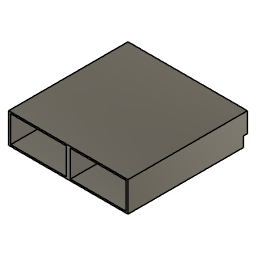
360degrees (Autodesk Fusion 360 design; units mm, degrees)
Autodesk Fusion 360 part; units mm, degrees
sketch "Sketch1" plane through (0, 0, 0) normal (0, 0, 1) x (1, 0, 0)
  line L0 (0, 0) -> (60, 0)
  line L1 (60, 0) -> (60, 60)
  line L2 (60, 60) -> (0, 60)
  line L3 (0, 60) -> (0, 0)
  dimension "d1" = 60
  dimension "d2" = 60
  constraint horizontal L0
  constraint vertical L1
  constraint horizontal L2
  constraint vertical L3
  constraint coincident L0.start L3.end
  measures "d1" distance of L0.start L0.end
  measures "d2" distance of L0.start L2.end
extrude "Extrude1" add sketch "Sketch1" along normal blind 15 makes body 1
sketch "Sketch2" plane through (0, 0, 0) normal (0, -1, 0) x (1, 0, 0)
  line L0 (0, 0) -> (60, 0)
  line L1 (60, 0) -> (60, 15)
  line L2 (60, 15) -> (0, 15)
  line L3 (0, 15) -> (0, 0)
  line L4 (30, 0) -> (30, 15)
  line L5 (1, 14.25) -> (29, 14.25)
  line L6 (29, 14.25) -> (29, 0.75)
  line L7 (29, 0.75) -> (1, 0.75)
  line L8 (1, 0.75) -> (1, 14.25)
  line L9 (1, 14.25) -> (0, 14.25)
  line L10 (29, 14.25) -> (30, 14.25)
  line L11 (1, 14.25) -> (1, 15)
  line L12 (1, 0.75) -> (1, 0)
  line L13 (31, 14.25) -> (59, 14.25)
  line L14 (59, 14.25) -> (59, 0.75)
  line L15 (59, 0.75) -> (31, 0.75)
  line L16 (31, 0.75) -> (31, 14.25)
  line L17 (31, 14.25) -> (30, 14.25)
  line L18 (31, 14.25) -> (31, 15)
  line L19 (31, 0.75) -> (31, 0)
  line L20 (59, 14.25) -> (60, 14.25)
  dimension "d5" = 28
  dimension "d6" = 13.5
  dimension "d9" = 28
  dimension "d10" = 13.5
  constraint midpoint L0 L4.start
  constraint midpoint L2 L4.end
  constraint horizontal L5
  constraint vertical L6
  constraint horizontal L7
  constraint vertical L8
  constraint coincident L3 L9.end
  constraint perpendicular L3 L9
  constraint coincident L4 L10.end
  constraint perpendicular L4 L10
  constraint equal L9 L10
  constraint coincident L2 L11.end
  constraint perpendicular L2 L11
  constraint coincident L0 L12.end
  constraint perpendicular L0 L12
  constraint equal L11 L12
  constraint horizontal L13
  constraint vertical L14
  constraint horizontal L15
  constraint vertical L16
  constraint perpendicular L4 L17
  constraint coincident L2 L18.end
  constraint perpendicular L2 L18
  constraint coincident L0 L19.end
  constraint perpendicular L0 L19
  constraint coincident L1 L20.end
  constraint perpendicular L1 L20
  constraint equal L17 L20
  constraint equal L18 L19
  measures "d5" distance of L5.start L5.end
  measures "d6" distance of L5.start L7.end
  measures "d9" distance of L13.start L13.end
  measures "d10" distance of L13.start L15.end
extrude "Extrude2" cut sketch "Sketch2" against normal blind 30 contours L5 L6 L7 L8 | L13 L14 L15 L16 bodies 1
sketch "Sketch4" plane through (0, 30, 0) normal (0, -1, 0) x (1, 0, 0)
  line L0 (31, 0.75) -> (59, 0.75)
  line L1 (59, 0.75) -> (59, 14.25)
  line L2 (59, 14.25) -> (31, 14.25)
  line L3 (31, 14.25) -> (31, 0.75)
  line L4 (31, 0.75) -> (59, 0.75)
  line L5 (59, 0.75) -> (59, 10.75)
  line L6 (59, 10.75) -> (31, 10.75)
  line L7 (31, 10.75) -> (31, 0.75)
  dimension "d13" = 10
  constraint horizontal L4
  constraint vertical L5
  constraint horizontal L6
  constraint vertical L7
  constraint coincident L0.start L3.end
  measures "d13" distance of L0.start L6.end
sketch "Sketch5" plane through (0, 30, 0) normal (0, -1, 0) x (1, 0, 0)
  line L0 (1, 0.75) -> (29, 0.75)
  line L1 (29, 0.75) -> (29, 14.25)
  line L2 (29, 14.25) -> (1, 14.25)
  line L3 (1, 14.25) -> (1, 0.75)
  line L4 (1, 0.75) -> (29, 0.75)
  line L5 (29, 0.75) -> (29, 10.75)
  line L6 (29, 10.75) -> (1, 10.75)
  line L7 (1, 10.75) -> (1, 0.75)
  dimension "d14" = 10
  constraint horizontal L4
  constraint vertical L5
  constraint horizontal L6
  constraint vertical L7
  constraint coincident L0.start L3.end
  measures "d14" distance of L0.start L6.end
sketch "Sketch6" plane through (0, 0, 0) normal (0, 0, -1) x (1, 0, 0)
  line L0 (0, 0) -> (0, -60)
  line L1 (0, -60) -> (60, -60)
  line L2 (60, -60) -> (60, 0)
  line L3 (60, 0) -> (0, 0)
  line L4 (0, -30) -> (60, -30)
  line L5 (1, -59) -> (59, -59)
  line L6 (59, -59) -> (59, -31)
  line L7 (59, -31) -> (1, -31)
  line L8 (1, -31) -> (1, -59)
  line L9 (1, -59) -> (0, -59)
  line L10 (59, -59) -> (60, -59)
  line L11 (59, -59) -> (59, -60)
  line L12 (59, -31) -> (59, -30)
  dimension "d15" = 58
  dimension "d16" = 28
  constraint midpoint L0 L4.start
  constraint midpoint L2 L4.end
  constraint horizontal L5
  constraint vertical L6
  constraint horizontal L7
  constraint vertical L8
  constraint coincident L0 L9.end
  constraint perpendicular L0 L9
  constraint coincident L2 L10.end
  constraint perpendicular L2 L10
  constraint coincident L1 L11.end
  constraint perpendicular L1 L11
  constraint coincident L4 L12.end
  constraint perpendicular L4 L12
  constraint equal L11 L12
  constraint equal L9 L10
  measures "d15" distance of L5.start L5.end
  measures "d16" distance of L5.start L7.end
extrude "Extrude3" cut sketch "Sketch6" against normal blind 13 contours L5 L6 L7 L8 bodies 1
extrude "Extrude4" cut sketch "Sketch5" sketch "Sketch4" against normal blind 5 contours L0 L1 L3 L4 L5 L6 L7 of sketch 2 contours L0 L1 L3 L4 L5 L6 L7 bodies 1
sketch "Sketch7" plane through (0, 60, 0) normal (0, 1, 0) x (-1, 0, 0)
  line L0 (-60, 0) -> (0, 0)
  line L1 (0, 0) -> (0, 15)
  line L2 (0, 15) -> (-60, 15)
  line L3 (-60, 15) -> (-60, 0)
  line L4 (-60, 0) -> (0, 0)
  line L5 (0, 0) -> (0, 5)
  line L6 (0, 5) -> (-60, 5)
  line L7 (-60, 5) -> (-60, 0)
  dimension "d21" = 5
  constraint horizontal L4
  constraint vertical L5
  constraint horizontal L6
  constraint vertical L7
  constraint coincident L0.start L3.end
  measures "d21" distance of L0.start L6.end
extrude "Extrude5" cut sketch "Sketch7" against normal blind 2 contours L0 L1 L3 L4 L5 L6 L7 bodies 1
copy_body "Body->Comp1" bodies 1 removing the originals makes body 2 in component "360degrees"
component "360degrees" placed x (1, 0, 0) y (0, 1, 0) z (0, 0, 1) at (0, 0, 0)
